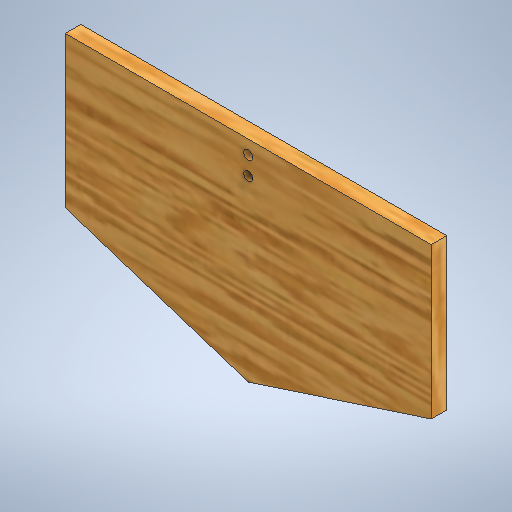
# Autodesk Inventor part: Bow_Tansform_Plate_No_Holes
Saved by Autodesk Inventor 2026.2 (Build 302298000, 298)
## iProperties
Created: 2026-07-14
Part Number: Bow_Tansform_Plate_No_Holes
Material: Plywood, Finish
Document SubType Name: Modeling
Designer: Taiye Raji
Density: 0.55 g/cm^3
Appearance: Plywood - New
Mass: 865.96 g
Surface Area: 1820.93 cm^2
Volume: 1574.47 cm^3
Author: Taiye Raji
Autodesk Inventor part; units mm, degrees
ref_plane "YZ Plane" through (0, 0, 0) normal (1, 0, 0) x (0, 1, 0)
ref_plane "XZ Plane" through (0, 0, 0) normal (0, 1, 0) x (-1, 0, 0)
ref_plane "XY Plane" through (0, 0, 0) normal (0, 0, 1) x (1, 0, 0)
sketch "Sketch1" plane through (0, 0, 0) normal (0, 0, 1) x (1, 0, 0)
  line L0 (0, 0) -> (0, 165.0161) construction
  line L1 (200, 230) -> (0, 230)
  line L2 (0, 0) -> (200, 0) construction
  line L3 (200, 230) -> (200, 64.9839)
  line L4 (200, 64.9839) -> (0, 0)
  line L5 (-200, 230) -> (0, 230)
  line L6 (-200, 230) -> (-200, 64.9839)
  line L7 (-200, 64.9839) -> (0, 0)
  circle A0 centre (0, 195) radius 5
  circle A1 centre (0, 215) radius 5
  dimension "d1" = 200
  dimension "d2" = 230
  dimension "d3" = 18
  dimension "d19" = 10
  dimension "d20" = 35
  dimension "d23" = 15
  constraints: 16 end point, 2 centre point, 2 parallel, 2 point on line, 2 symmetric about line, 2 vertical, 1 equal radius, 1 horizontal, 1 perpendicular, 1 vertical alignment
  measures "d1" distance of L1.start L1.end
  measures "d2" distance from line of L0.start L1
  measures "d3" angle of L2 L4
  measures "d19" diameter of A0
  measures "d20" distance from line of A0.centre L1
  measures "d23" distance from line of A1.centre L5
extrude "Extrusion1" add sketch "Sketch1" against normal blind 17
sketch "Sketch2" plane through (0, 0, 0) normal (0, 0, 1) x (1, 0, 0)
  line L0 (0, 0) -> (0, 20)
  line L1 (0, 0) -> (200, 64.9839) projected
  line L2 (200, 64.9839) -> (200, 84.9839)
  line L3 (200, 230) -> (200, 64.9839) projected
  line L4 (-61.5537, 0) -> (200, 84.9839)
  line L5 (-200, 230) -> (200, 230) projected
  line L6 (200, 230) -> (180, 230)
  line L7 (180, 78.4855) -> (180, 230)
  line L8 (180, 230) -> (200, 230)
  line L9 (0, 0) -> (200, 64.9839)
  line L10 (0, 0) -> (128.5875, 0)
  line L11 (200, 64.9839) -> (0, 0) projected
  line L12 (200, 64.9839) -> (194.1221, 83.0741)
  line L13 (0, 0) -> (-5.8779, 18.0902)
  line L14 (0, 230) -> (0, 20)
  dimension "d7" = 20
  dimension "d8" = 20
  dimension "d9" = 151.5145
  dimension "d10" = 128.5875
  dimension "d11" = 90
  dimension "d12" = 90
  dimension "d13" = 210
  constraints: 22 end point, 7 point on line, 2 horizontal, 2 vertical, 1 midpoint, 1 parallel, 1 perpendicular
  measures "d7" distance of L1.end L2.end
  measures "d8" distance between parallel lines of L3 L7
  measures "d9" distance of L7.start L6.end
  measures "d10" distance of L0.start L10.end
  measures "d11" angle of L1 L12
  measures "d12" angle of L1 L13
  measures "d13" distance of L14.start L0.end
body "Solid1"
